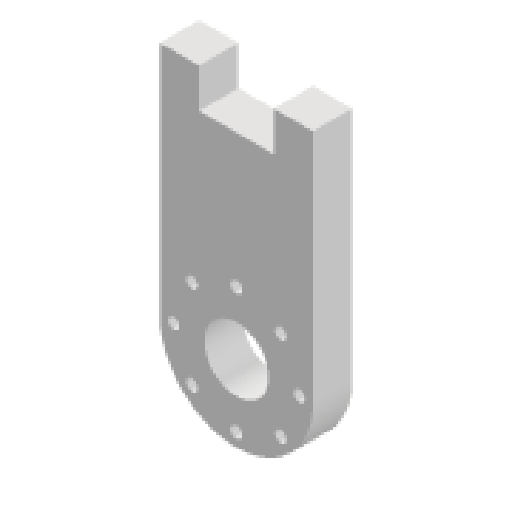
# Autodesk Inventor part: FootL
Saved by Autodesk Inventor 2025.2 (Build 292293000, 293)
## iProperties
Created: 2025-06-24
Part Number: FootL
Material: Generic
Document SubType Name: Modeling
Designer: ricoa
Density: 1 g/cm^3
Appearance: Default
Author: ricoa
Autodesk Inventor part; units mm, degrees
ref_plane "YZ Plane" through (0, 0, 0) normal (1, 0, 0) x (0, 1, 0)
ref_plane "XZ Plane" through (0, 0, 0) normal (0, 1, 0) x (-1, 0, 0)
ref_plane "XY Plane" through (0, 0, 0) normal (0, 0, 1) x (1, 0, 0)
sketch "Sketch1" plane through (0, 0, 0) normal (0, 0, 1) x (1, 0, 0)
  arc A0 (-8.4774, -4.8163) -> (8.5442, -4.6967) centre (0, 0) ccw
  circle A1 centre (0, 0) radius 4 projected
  circle A2 centre (-5.6569, 5.6569) radius 0.75 projected
  circle A3 centre (-8, 0) radius 0.75 projected
  circle A4 centre (-5.6569, -5.6569) radius 0.75 projected
  circle A5 centre (0, -8) radius 0.75 projected
  circle A6 centre (5.6569, -5.6569) radius 0.75 projected
  circle A7 centre (8, 0) radius 0.75 projected
  circle A8 centre (5.6569, 5.6569) radius 0.75 projected
  circle A9 centre (0, 8) radius 0.75 projected
  circle A10 centre (0, 0) radius 4.1
  line L0 (0, 0) -> (0, 25) construction
  line L1 (23.875, -35.6314) -> (23.875, -0.8979) construction
  line L2 (-24.125, -35.6314) -> (-24.125, -0.8979) construction
  line L3 (-9.75, 0) -> (-9.75, 20)
  arc A11 (-9.75, 0) -> (9.75, 0) centre (0, 0) ccw
  line L4 (9.75, 0) -> (9.75, 20)
  line L5 (9.75, 20) -> (9.75, 25)
  line L6 (9.75, 25) -> (9.75, 30)
  line L7 (9.75, 30) -> (4.75, 30)
  line L8 (4.75, 30) -> (4.75, 25)
  line L9 (-9.75, 20) -> (-9.75, 30)
  line L10 (-9.75, 30) -> (-4.75, 30)
  line L11 (-4.75, 30) -> (-4.75, 25)
  line L12 (-4.75, 25) -> (4.75, 25)
  point P0 (8, -5.5734)
  point P1 (-8, -5.5734)
  dimension "d0" = 8.2
  dimension "d1" = 25
  dimension "d8" = 5
  dimension "d9" = 5
  dimension "d10" = 5
  dimension "d25" = 5
  dimension "d26" = 5
  constraints: 22 end point, 7 point on circle, 5 perpendicular, 4 coincident, 3 centre point, 3 tangent, 3 vertical, 1 midpoint, 1 point on line
  measures "d0" diameter of A10
  measures "d1" distance of L0.start L0.end
  measures "d8" distance of L5.end L6.end
  measures "d9" distance of L6.end L7.end
  measures "d10" distance of L9.end L10.end
  measures "d25" distance between parallel lines of L12 L7
  measures "d26" distance between parallel lines of L10 L12
extrude "Extrusion1" add sketch "Sketch1" along normal blind 5 contours A11 L3 L9 L10 L11 L12 L8 L7 L6 L5 L4 A0
body "Solid1"
